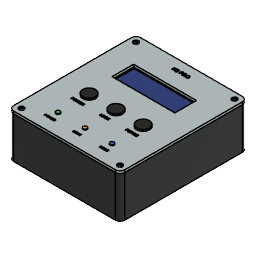
before_v2_edit (Autodesk Fusion 360 design; units mm, degrees)
part number: 2026-09-27-10-19-20-342
part number: 2026-09-27-10-19-20-901
part number: 2026-09-27-10-19-24-013
part number: 2026-09-27-10-19-37-450
part number: 2026-09-27-10-19-39-666
part number: 2026-09-27-10-19-42-130
part number: 2026-09-27-10-19-44-621
part number: 2026-09-27-10-19-47-336
Autodesk Fusion 360 part; units mm, degrees
sketch "Outer shell sketch" plane through (0, 0, 0) normal (0, 0, 1) x (1, 0, 0) in component "01 BASE - PCB at bottom"
  line L0 (6, 0) -> (134, 0)
  line L1 (140, 6) -> (140, 154)
  line L2 (134, 160) -> (6, 160)
  line L3 (0, 154) -> (0, 6)
  arc A0 (134, 0) -> (140, 6) centre (134, 6) ccw
  arc A1 (140, 154) -> (134, 160) centre (134, 154) ccw
  arc A2 (6, 160) -> (0, 154) centre (6, 154) ccw
  arc A3 (0, 6) -> (6, 0) centre (6, 6) ccw
extrude "Outer shell" add sketch "Outer shell sketch" along normal blind 52 makes body 1 in component "01 BASE - PCB at bottom"
ref_plane "WorkPlane1" through (0, 0, 3) normal (0, 0, 1) x (1, 0, 0) in component "01 BASE - PCB at bottom"
sketch "Hollow cavity sketch" plane through (0, 0, 3) normal (0, 0, 1) x (1, 0, 0) in component "01 BASE - PCB at bottom"
  line L0 (6, 3) -> (134, 3)
  line L1 (137, 6) -> (137, 154)
  line L2 (134, 157) -> (6, 157)
  line L3 (3, 154) -> (3, 6)
  arc A0 (134, 3) -> (137, 6) centre (134, 6) ccw
  arc A1 (137, 154) -> (134, 157) centre (134, 154) ccw
  arc A2 (6, 157) -> (3, 154) centre (6, 154) ccw
  arc A3 (3, 6) -> (6, 3) centre (6, 6) ccw
extrude "Hollow cavity" cut sketch "Hollow cavity sketch" along normal blind 50 bodies 1 in component "01 BASE - PCB at bottom"
ref_plane "WorkPlane2" through (0, 0, 3) normal (0, 0, 1) x (1, 0, 0) in component "01 BASE - PCB at bottom"
sketch "Four lid screw pillars" plane through (0, 0, 3) normal (0, 0, 1) x (1, 0, 0) in component "01 BASE - PCB at bottom"
  line L0 (3, 3) -> (13, 3)
  line L1 (13, 3) -> (13, 13)
  line L2 (13, 13) -> (3, 13)
  line L3 (3, 13) -> (3, 3)
  line L4 (127, 3) -> (137, 3)
  line L5 (137, 3) -> (137, 13)
  line L6 (137, 13) -> (127, 13)
  line L7 (127, 13) -> (127, 3)
  line L8 (3, 147) -> (13, 147)
  line L9 (13, 147) -> (13, 157)
  line L10 (13, 157) -> (3, 157)
  line L11 (3, 157) -> (3, 147)
  line L12 (127, 147) -> (137, 147)
  line L13 (137, 147) -> (137, 157)
  line L14 (137, 157) -> (127, 157)
  line L15 (127, 157) -> (127, 147)
extrude "Lid pillars" add sketch "Four lid screw pillars" along normal blind 49 bodies 1 in component "01 BASE - PCB at bottom"
ref_plane "WorkPlane3" through (0, 0, 40) normal (0, 0, 1) x (1, 0, 0) in component "01 BASE - PCB at bottom"
sketch "M3 lid pilot holes sketch" plane through (0, 0, 40) normal (0, 0, 1) x (1, 0, 0) in component "01 BASE - PCB at bottom"
  circle A0 centre (8, 8) radius 1.25
  circle A1 centre (132, 8) radius 1.25
  circle A2 centre (8, 152) radius 1.25
  circle A3 centre (132, 152) radius 1.25
  dimension "d17" = 2.5
  dimension "d18" = 2.5
  dimension "d19" = 2.5
  dimension "d20" = 2.5
  measures "d17" diameter of A0
  measures "d18" diameter of A1
  measures "d19" diameter of A2
  measures "d20" diameter of A3
extrude "M3 lid pilot holes" cut sketch "M3 lid pilot holes sketch" along normal blind 12.1 bodies 1 in component "01 BASE - PCB at bottom"
ref_plane "WorkPlane4" through (0, 0, 3) normal (0, 0, 1) x (1, 0, 0) in component "01 BASE - PCB at bottom"
sketch "PCB support pads" plane through (0, 0, 3) normal (0, 0, 1) x (1, 0, 0) in component "01 BASE - PCB at bottom"
  line L0 (23, 40) -> (29, 40)
  line L1 (29, 40) -> (29, 50)
  line L2 (29, 50) -> (23, 50)
  line L3 (23, 50) -> (23, 40)
  line L4 (23, 110) -> (29, 110)
  line L5 (29, 110) -> (29, 120)
  line L6 (29, 120) -> (23, 120)
  line L7 (23, 120) -> (23, 110)
  line L8 (111, 40) -> (117, 40)
  line L9 (117, 40) -> (117, 50)
  line L10 (117, 50) -> (111, 50)
  line L11 (111, 50) -> (111, 40)
  line L12 (111, 110) -> (117, 110)
  line L13 (117, 110) -> (117, 120)
  line L14 (117, 120) -> (111, 120)
  line L15 (111, 120) -> (111, 110)
extrude "PCB supports z8" add sketch "PCB support pads" along normal blind 5 bodies 1 in component "01 BASE - PCB at bottom"
ref_plane "WorkPlane5" through (0, 0, 3) normal (0, 0, 1) x (1, 0, 0) in component "01 BASE - PCB at bottom"
sketch "PCB lateral guides" plane through (0, 0, 3) normal (0, 0, 1) x (1, 0, 0) in component "01 BASE - PCB at bottom"
  line L0 (22.2, 40) -> (24.6, 40)
  line L1 (24.6, 40) -> (24.6, 50)
  line L2 (24.6, 50) -> (22.2, 50)
  line L3 (22.2, 50) -> (22.2, 40)
  line L4 (22.2, 110) -> (24.6, 110)
  line L5 (24.6, 110) -> (24.6, 120)
  line L6 (24.6, 120) -> (22.2, 120)
  line L7 (22.2, 120) -> (22.2, 110)
  line L8 (115.4, 40) -> (117.8, 40)
  line L9 (117.8, 40) -> (117.8, 50)
  line L10 (117.8, 50) -> (115.4, 50)
  line L11 (115.4, 50) -> (115.4, 40)
  line L12 (115.4, 110) -> (117.8, 110)
  line L13 (117.8, 110) -> (117.8, 120)
  line L14 (117.8, 120) -> (115.4, 120)
  line L15 (115.4, 120) -> (115.4, 110)
  line L16 (55, 27.2) -> (85, 27.2)
  line L17 (85, 27.2) -> (85, 29.6)
  line L18 (85, 29.6) -> (55, 29.6)
  line L19 (55, 29.6) -> (55, 27.2)
  line L20 (55, 130.4) -> (85, 130.4)
  line L21 (85, 130.4) -> (85, 132.8)
  line L22 (85, 132.8) -> (55, 132.8)
  line L23 (55, 132.8) -> (55, 130.4)
extrude "Board edge guides clearance 0.4" add sketch "PCB lateral guides" along normal blind 6.6 bodies 1 in component "01 BASE - PCB at bottom"
ref_plane "WorkPlane6" through (0, 0, 3) normal (0, 0, 1) x (1, 0, 0) in component "01 BASE - PCB at bottom"
sketch "Clamp screw pedestals sketch" plane through (0, 0, 3) normal (0, 0, 1) x (1, 0, 0) in component "01 BASE - PCB at bottom"
  circle A0 centre (20, 45) radius 4
  circle A1 centre (120, 45) radius 4
  circle A2 centre (20, 115) radius 4
  circle A3 centre (120, 115) radius 4
extrude "Clamp screw pedestals" add sketch "Clamp screw pedestals sketch" along normal blind 6.6 bodies 1 in component "01 BASE - PCB at bottom"
ref_plane "WorkPlane7" through (0, 0, 3.1) normal (0, 0, 1) x (1, 0, 0) in component "01 BASE - PCB at bottom"
sketch "M3 clamp pilots sketch" plane through (0, 0, 3.1) normal (0, 0, 1) x (1, 0, 0) in component "01 BASE - PCB at bottom"
  circle A0 centre (20, 45) radius 1.25
  circle A1 centre (120, 45) radius 1.25
  circle A2 centre (20, 115) radius 1.25
  circle A3 centre (120, 115) radius 1.25
  dimension "d37" = 2.5
  dimension "d38" = 2.5
  dimension "d39" = 2.5
  dimension "d40" = 2.5
  measures "d37" diameter of A0
  measures "d38" diameter of A1
  measures "d39" diameter of A2
  measures "d40" diameter of A3
extrude "M3 clamp pilots" cut sketch "M3 clamp pilots sketch" along normal blind 6.6 bodies 1 in component "01 BASE - PCB at bottom"
ref_plane "WorkPlane1" through (0, 0, 52) normal (0, 0, 1) x (1, 0, 0) in component "02 LID - LCD buttons LEDs"
sketch "Lid plate sketch" plane through (0, 0, 52) normal (0, 0, 1) x (1, 0, 0) in component "02 LID - LCD buttons LEDs"
  line L0 (6, 0) -> (134, 0)
  line L1 (140, 6) -> (140, 154)
  line L2 (134, 160) -> (6, 160)
  line L3 (0, 154) -> (0, 6)
  arc A0 (134, 0) -> (140, 6) centre (134, 6) ccw
  arc A1 (140, 154) -> (134, 160) centre (134, 154) ccw
  arc A2 (6, 160) -> (0, 154) centre (6, 154) ccw
  arc A3 (0, 6) -> (6, 0) centre (6, 6) ccw
extrude "Lid plate" add sketch "Lid plate sketch" along normal blind 3 separate body makes body 2 in component "02 LID - LCD buttons LEDs"
ref_plane "WorkPlane2" through (0, 0, 48) normal (0, 0, 1) x (1, 0, 0) in component "02 LID - LCD buttons LEDs"
sketch "Locating lip segments - 0.3 clearance" plane through (0, 0, 48) normal (0, 0, 1) x (1, 0, 0) in component "02 LID - LCD buttons LEDs"
  line L0 (3.3, 16) -> (5.3, 16)
  line L1 (5.3, 16) -> (5.3, 144)
  line L2 (5.3, 144) -> (3.3, 144)
  line L3 (3.3, 144) -> (3.3, 16)
  line L4 (134.7, 16) -> (136.7, 16)
  line L5 (136.7, 16) -> (136.7, 144)
  line L6 (136.7, 144) -> (134.7, 144)
  line L7 (134.7, 144) -> (134.7, 16)
  line L8 (16, 3.3) -> (124, 3.3)
  line L9 (124, 3.3) -> (124, 5.3)
  line L10 (124, 5.3) -> (16, 5.3)
  line L11 (16, 5.3) -> (16, 3.3)
  line L12 (16, 154.7) -> (124, 154.7)
  line L13 (124, 154.7) -> (124, 156.7)
  line L14 (124, 156.7) -> (16, 156.7)
  line L15 (16, 156.7) -> (16, 154.7)
extrude "Locating lips" add sketch "Locating lip segments - 0.3 clearance" along normal blind 4 bodies 2 in component "02 LID - LCD buttons LEDs"
ref_plane "WorkPlane3" through (0, 0, 51.9) normal (0, 0, 1) x (1, 0, 0) in component "02 LID - LCD buttons LEDs"
sketch "M3 lid through holes sketch" plane through (0, 0, 51.9) normal (0, 0, 1) x (1, 0, 0) in component "02 LID - LCD buttons LEDs"
  circle A0 centre (8, 8) radius 1.7
  circle A1 centre (132, 8) radius 1.7
  circle A2 centre (8, 152) radius 1.7
  circle A3 centre (132, 152) radius 1.7
  dimension "d53" = 3.4
  dimension "d54" = 3.4
  dimension "d55" = 3.4
  dimension "d56" = 3.4
  measures "d53" diameter of A0
  measures "d54" diameter of A1
  measures "d55" diameter of A2
  measures "d56" diameter of A3
extrude "M3 lid through holes" cut sketch "M3 lid through holes sketch" along normal blind 3.2 bodies 2 in component "02 LID - LCD buttons LEDs"
ref_plane "WorkPlane4" through (0, 0, 53.8) normal (0, 0, 1) x (1, 0, 0) in component "02 LID - LCD buttons LEDs"
sketch "Screw head pockets sketch" plane through (0, 0, 53.8) normal (0, 0, 1) x (1, 0, 0) in component "02 LID - LCD buttons LEDs"
  circle A0 centre (8, 8) radius 3.2
  circle A1 centre (132, 8) radius 3.2
  circle A2 centre (8, 152) radius 3.2
  circle A3 centre (132, 152) radius 3.2
extrude "Screw head pockets" cut sketch "Screw head pockets sketch" along normal blind 1.3 bodies 2 in component "02 LID - LCD buttons LEDs"
ref_plane "WorkPlane5" through (0, 0, 51.9) normal (0, 0, 1) x (1, 0, 0) in component "02 LID - LCD buttons LEDs"
sketch "LCD viewing aperture sketch" plane through (0, 0, 51.9) normal (0, 0, 1) x (1, 0, 0) in component "02 LID - LCD buttons LEDs"
  line L0 (30.5, 99.5) -> (109.5, 99.5)
  line L1 (109.5, 99.5) -> (109.5, 126.5)
  line L2 (109.5, 126.5) -> (30.5, 126.5)
  line L3 (30.5, 126.5) -> (30.5, 99.5)
extrude "LCD viewing aperture" cut sketch "LCD viewing aperture sketch" along normal blind 3.2 bodies 2 in component "02 LID - LCD buttons LEDs"
ref_plane "WorkPlane6" through (0, 0, 42) normal (0, 0, 1) x (1, 0, 0) in component "02 LID - LCD buttons LEDs"
sketch "LCD underside spacers sketch" plane through (0, 0, 42) normal (0, 0, 1) x (1, 0, 0) in component "02 LID - LCD buttons LEDs"
  circle A0 centre (23.5, 85.5) radius 3.5
  circle A1 centre (116.5, 85.5) radius 3.5
  circle A2 centre (23.5, 140.5) radius 3.5
  circle A3 centre (116.5, 140.5) radius 3.5
extrude "LCD underside spacers" add sketch "LCD underside spacers sketch" along normal blind 10 bodies 2 in component "02 LID - LCD buttons LEDs"
ref_plane "WorkPlane7" through (0, 0, 41.9) normal (0, 0, 1) x (1, 0, 0) in component "02 LID - LCD buttons LEDs"
sketch "LCD M3 pilot holes sketch" plane through (0, 0, 41.9) normal (0, 0, 1) x (1, 0, 0) in component "02 LID - LCD buttons LEDs"
  circle A0 centre (23.5, 85.5) radius 1.25
  circle A1 centre (116.5, 85.5) radius 1.25
  circle A2 centre (23.5, 140.5) radius 1.25
  circle A3 centre (116.5, 140.5) radius 1.25
  dimension "d73" = 2.5
  dimension "d74" = 2.5
  dimension "d75" = 2.5
  dimension "d76" = 2.5
  measures "d73" diameter of A0
  measures "d74" diameter of A1
  measures "d75" diameter of A2
  measures "d76" diameter of A3
extrude "LCD M3 pilot holes" cut sketch "LCD M3 pilot holes sketch" along normal blind 8.1 bodies 2 in component "02 LID - LCD buttons LEDs"
ref_plane "WorkPlane8" through (0, 0, 51.9) normal (0, 0, 1) x (1, 0, 0) in component "02 LID - LCD buttons LEDs"
sketch "Three panel buttons sketch" plane through (0, 0, 51.9) normal (0, 0, 1) x (1, 0, 0) in component "02 LID - LCD buttons LEDs"
  circle A0 centre (36, 65) radius 6.1
  circle A1 centre (70, 65) radius 6.1
  circle A2 centre (104, 65) radius 6.1
  dimension "d81" = 12.2
  dimension "d82" = 12.2
  dimension "d83" = 12.2
  measures "d81" diameter of A0
  measures "d82" diameter of A1
  measures "d83" diameter of A2
extrude "Three panel buttons" cut sketch "Three panel buttons sketch" along normal blind 3.2 bodies 2 in component "02 LID - LCD buttons LEDs"
ref_plane "WorkPlane9" through (0, 0, 51.9) normal (0, 0, 1) x (1, 0, 0) in component "02 LID - LCD buttons LEDs"
sketch "Three indicator LEDs sketch" plane through (0, 0, 51.9) normal (0, 0, 1) x (1, 0, 0) in component "02 LID - LCD buttons LEDs"
  circle A0 centre (36, 26) radius 2.6
  circle A1 centre (70, 26) radius 2.6
  circle A2 centre (104, 26) radius 2.6
  dimension "d88" = 5.2
  dimension "d89" = 5.2
  dimension "d90" = 5.2
  measures "d88" diameter of A0
  measures "d89" diameter of A1
  measures "d90" diameter of A2
extrude "Three indicator LEDs" cut sketch "Three indicator LEDs sketch" along normal blind 3.2 bodies 2 in component "02 LID - LCD buttons LEDs"
ref_plane "WorkPlane10" through (0, 0, 55) normal (0, 0, 1) x (1, 0, 0) in component "02 LID - LCD buttons LEDs"
sketch "Engraving H2 PRO" plane through (0, 0, 55) normal (0, 0, 1) x (1, 0, 0) in component "02 LID - LCD buttons LEDs"
  line L0 (37.5, 144.5) -> (102.5, 144.5) construction
  line L1 (102.5, 144.5) -> (102.5, 149.5) construction
  line L2 (102.5, 149.5) -> (37.5, 149.5) construction
  line L3 (37.5, 149.5) -> (37.5, 144.5) construction
  dimension "d95" = 4
  dimension "d96" = 0
  text T0 "H2 PRO" font "Arial" height 4 align centre middle in box 65 x 5 at (37.5, 144.5) x (1, 0) y (0, 1) spacing 1 kerned
extrude "Engrave H2 PRO" cut sketch "Engraving H2 PRO" against normal blind 0.4 text T0 bodies 2 in component "02 LID - LCD buttons LEDs"
ref_plane "WorkPlane11" through (0, 0, 55) normal (0, 0, 1) x (1, 0, 0) in component "02 LID - LCD buttons LEDs"
sketch "Engraving POWER" plane through (0, 0, 55) normal (0, 0, 1) x (1, 0, 0) in component "02 LID - LCD buttons LEDs"
  line L0 (21, 48.5) -> (51, 48.5) construction
  line L1 (51, 48.5) -> (51, 53.5) construction
  line L2 (51, 53.5) -> (21, 53.5) construction
  line L3 (21, 53.5) -> (21, 48.5) construction
  dimension "d101" = 3
  text T0 "POWER" font "Arial" height 3 align centre middle in box 30 x 5 at (21, 48.5) x (1, 0) y (0, 1) spacing 1 kerned
extrude "Engrave POWER" cut sketch "Engraving POWER" against normal blind 0.4 text T0 bodies 2 in component "02 LID - LCD buttons LEDs"
ref_plane "WorkPlane12" through (0, 0, 55) normal (0, 0, 1) x (1, 0, 0) in component "02 LID - LCD buttons LEDs"
sketch "Engraving LOCK" plane through (0, 0, 55) normal (0, 0, 1) x (1, 0, 0) in component "02 LID - LCD buttons LEDs"
  line L0 (55, 48.5) -> (85, 48.5) construction
  line L1 (85, 48.5) -> (85, 53.5) construction
  line L2 (85, 53.5) -> (55, 53.5) construction
  line L3 (55, 53.5) -> (55, 48.5) construction
  dimension "d107" = 3
  text T0 "LOCK" font "Arial" height 3 align centre middle in box 30 x 5 at (55, 48.5) x (1, 0) y (0, 1) spacing 1 kerned
extrude "Engrave LOCK" cut sketch "Engraving LOCK" against normal blind 0.4 text T0 bodies 2 in component "02 LID - LCD buttons LEDs"
ref_plane "WorkPlane13" through (0, 0, 55) normal (0, 0, 1) x (1, 0, 0) in component "02 LID - LCD buttons LEDs"
sketch "Engraving PURGE" plane through (0, 0, 55) normal (0, 0, 1) x (1, 0, 0) in component "02 LID - LCD buttons LEDs"
  line L0 (89, 48.5) -> (119, 48.5) construction
  line L1 (119, 48.5) -> (119, 53.5) construction
  line L2 (119, 53.5) -> (89, 53.5) construction
  line L3 (89, 53.5) -> (89, 48.5) construction
  dimension "d113" = 3
  text T0 "PURGE" font "Arial" height 3 align centre middle in box 30 x 5 at (89, 48.5) x (1, 0) y (0, 1) spacing 1 kerned
extrude "Engrave PURGE" cut sketch "Engraving PURGE" against normal blind 0.4 text T0 bodies 2 in component "02 LID - LCD buttons LEDs"
ref_plane "WorkPlane14" through (0, 0, 55) normal (0, 0, 1) x (1, 0, 0) in component "02 LID - LCD buttons LEDs"
sketch "Engraving POWER (1)" plane through (0, 0, 55) normal (0, 0, 1) x (1, 0, 0) in component "02 LID - LCD buttons LEDs"
  line L0 (21, 13.5) -> (51, 13.5) construction
  line L1 (51, 13.5) -> (51, 18.5) construction
  line L2 (51, 18.5) -> (21, 18.5) construction
  line L3 (21, 18.5) -> (21, 13.5) construction
  dimension "d119" = 2.5
  text T0 "POWER" font "Arial" height 2.5 align centre middle in box 30 x 5 at (21, 13.5) x (1, 0) y (0, 1) spacing 1 kerned
extrude "Engrave POWER (1)" cut sketch "Engraving POWER (1)" against normal blind 0.4 text T0 bodies 2 in component "02 LID - LCD buttons LEDs"
ref_plane "WorkPlane15" through (0, 0, 55) normal (0, 0, 1) x (1, 0, 0) in component "02 LID - LCD buttons LEDs"
sketch "Engraving LOCK (1)" plane through (0, 0, 55) normal (0, 0, 1) x (1, 0, 0) in component "02 LID - LCD buttons LEDs"
  line L0 (55, 13.5) -> (85, 13.5) construction
  line L1 (85, 13.5) -> (85, 18.5) construction
  line L2 (85, 18.5) -> (55, 18.5) construction
  line L3 (55, 18.5) -> (55, 13.5) construction
  dimension "d125" = 2.5
  text T0 "LOCK" font "Arial" height 2.5 align centre middle in box 30 x 5 at (55, 13.5) x (1, 0) y (0, 1) spacing 1 kerned
extrude "Engrave LOCK (1)" cut sketch "Engraving LOCK (1)" against normal blind 0.4 text T0 bodies 2 in component "02 LID - LCD buttons LEDs"
ref_plane "WorkPlane16" through (0, 0, 55) normal (0, 0, 1) x (1, 0, 0) in component "02 LID - LCD buttons LEDs"
sketch "Engraving MODE" plane through (0, 0, 55) normal (0, 0, 1) x (1, 0, 0) in component "02 LID - LCD buttons LEDs"
  line L0 (89, 13.5) -> (119, 13.5) construction
  line L1 (119, 13.5) -> (119, 18.5) construction
  line L2 (119, 18.5) -> (89, 18.5) construction
  line L3 (89, 18.5) -> (89, 13.5) construction
  dimension "d131" = 2.5
  text T0 "MODE" font "Arial" height 2.5 align centre middle in box 30 x 5 at (89, 13.5) x (1, 0) y (0, 1) spacing 1 kerned
extrude "Engrave MODE" cut sketch "Engraving MODE" against normal blind 0.4 text T0 bodies 2 in component "02 LID - LCD buttons LEDs"
ref_plane "WorkPlane1" through (0, 0, 9.6) normal (0, 0, 1) x (1, 0, 0) in component "03 PCB clamp 1"
sketch "Removable edge clamp sketch" plane through (0, 0, 9.6) normal (0, 0, 1) x (1, 0, 0) in component "03 PCB clamp 1"
  line L0 (17, 40) -> (27.5, 40)
  line L1 (28.5, 41) -> (28.5, 49)
  line L2 (27.5, 50) -> (17, 50)
  line L3 (16, 49) -> (16, 41)
  arc A0 (27.5, 40) -> (28.5, 41) centre (27.5, 41) ccw
  arc A1 (28.5, 49) -> (27.5, 50) centre (27.5, 49) ccw
  arc A2 (17, 50) -> (16, 49) centre (17, 49) ccw
  arc A3 (16, 41) -> (17, 40) centre (17, 41) ccw
extrude "Removable edge clamp" add sketch "Removable edge clamp sketch" along normal blind 2.5 separate body makes body 3 in component "03 PCB clamp 1"
ref_plane "WorkPlane2" through (0, 0, 9.5) normal (0, 0, 1) x (1, 0, 0) in component "03 PCB clamp 1"
sketch "Clamp screw clearance sketch" plane through (0, 0, 9.5) normal (0, 0, 1) x (1, 0, 0) in component "03 PCB clamp 1"
  circle A0 centre (20, 45) radius 1.7
  dimension "d141" = 3.4
  measures "d141" diameter of A0
extrude "Clamp screw clearance" cut sketch "Clamp screw clearance sketch" along normal blind 2.7 bodies 3 in component "03 PCB clamp 1"
ref_plane "WorkPlane1" through (0, 0, 9.6) normal (0, 0, 1) x (1, 0, 0) in component "03 PCB clamp 2"
sketch "Removable edge clamp sketch (2)" plane through (0, 0, 9.6) normal (0, 0, 1) x (1, 0, 0) in component "03 PCB clamp 2"
  line L0 (112.5, 40) -> (123, 40)
  line L1 (124, 41) -> (124, 49)
  line L2 (123, 50) -> (112.5, 50)
  line L3 (111.5, 49) -> (111.5, 41)
  arc A0 (123, 40) -> (124, 41) centre (123, 41) ccw
  arc A1 (124, 49) -> (123, 50) centre (123, 49) ccw
  arc A2 (112.5, 50) -> (111.5, 49) centre (112.5, 49) ccw
  arc A3 (111.5, 41) -> (112.5, 40) centre (112.5, 41) ccw
extrude "Removable edge clamp'" add sketch "Removable edge clamp sketch (2)" along normal blind 2.5 separate body makes body 4 in component "03 PCB clamp 2"
ref_plane "WorkPlane2" through (0, 0, 9.5) normal (0, 0, 1) x (1, 0, 0) in component "03 PCB clamp 2"
sketch "Clamp screw clearance sketch (2)" plane through (0, 0, 9.5) normal (0, 0, 1) x (1, 0, 0) in component "03 PCB clamp 2"
  circle A0 centre (120, 45) radius 1.7
  dimension "d150" = 3.4
  measures "d150" diameter of A0
extrude "Clamp screw clearance'" cut sketch "Clamp screw clearance sketch (2)" along normal blind 2.7 bodies 4 in component "03 PCB clamp 2"
ref_plane "WorkPlane1" through (0, 0, 9.6) normal (0, 0, 1) x (1, 0, 0) in component "03 PCB clamp 3"
sketch "Removable edge clamp sketch (3)" plane through (0, 0, 9.6) normal (0, 0, 1) x (1, 0, 0) in component "03 PCB clamp 3"
  line L0 (17, 110) -> (27.5, 110)
  line L1 (28.5, 111) -> (28.5, 119)
  line L2 (27.5, 120) -> (17, 120)
  line L3 (16, 119) -> (16, 111)
  arc A0 (27.5, 110) -> (28.5, 111) centre (27.5, 111) ccw
  arc A1 (28.5, 119) -> (27.5, 120) centre (27.5, 119) ccw
  arc A2 (17, 120) -> (16, 119) centre (17, 119) ccw
  arc A3 (16, 111) -> (17, 110) centre (17, 111) ccw
extrude "Removable edge clamp''" add sketch "Removable edge clamp sketch (3)" along normal blind 2.5 separate body makes body 5 in component "03 PCB clamp 3"
ref_plane "WorkPlane2" through (0, 0, 9.5) normal (0, 0, 1) x (1, 0, 0) in component "03 PCB clamp 3"
sketch "Clamp screw clearance sketch (3)" plane through (0, 0, 9.5) normal (0, 0, 1) x (1, 0, 0) in component "03 PCB clamp 3"
  circle A0 centre (20, 115) radius 1.7
  dimension "d159" = 3.4
  measures "d159" diameter of A0
extrude "Clamp screw clearance''" cut sketch "Clamp screw clearance sketch (3)" along normal blind 2.7 bodies 5 in component "03 PCB clamp 3"
ref_plane "WorkPlane1" through (0, 0, 9.6) normal (0, 0, 1) x (1, 0, 0) in component "03 PCB clamp 4"
sketch "Removable edge clamp sketch (4)" plane through (0, 0, 9.6) normal (0, 0, 1) x (1, 0, 0) in component "03 PCB clamp 4"
  line L0 (112.5, 110) -> (123, 110)
  line L1 (124, 111) -> (124, 119)
  line L2 (123, 120) -> (112.5, 120)
  line L3 (111.5, 119) -> (111.5, 111)
  arc A0 (123, 110) -> (124, 111) centre (123, 111) ccw
  arc A1 (124, 119) -> (123, 120) centre (123, 119) ccw
  arc A2 (112.5, 120) -> (111.5, 119) centre (112.5, 119) ccw
  arc A3 (111.5, 111) -> (112.5, 110) centre (112.5, 111) ccw
extrude "Removable edge clamp'''" add sketch "Removable edge clamp sketch (4)" along normal blind 2.5 separate body makes body 6 in component "03 PCB clamp 4"
ref_plane "WorkPlane2" through (0, 0, 9.5) normal (0, 0, 1) x (1, 0, 0) in component "03 PCB clamp 4"
sketch "Clamp screw clearance sketch (4)" plane through (0, 0, 9.5) normal (0, 0, 1) x (1, 0, 0) in component "03 PCB clamp 4"
  circle A0 centre (120, 115) radius 1.7
  dimension "d168" = 3.4
  measures "d168" diameter of A0
extrude "Clamp screw clearance'''" cut sketch "Clamp screw clearance sketch (4)" along normal blind 2.7 bodies 6 in component "03 PCB clamp 4"
ref_plane "WorkPlane1" through (0, 0, 8) normal (0, 0, 1) x (1, 0, 0) in component "90 REFERENCES - DO NOT PRINT"
sketch "Main PCB 90x100 reference sketch" plane through (0, 0, 8) normal (0, 0, 1) x (1, 0, 0) in component "90 REFERENCES - DO NOT PRINT"
  line L0 (25, 30) -> (115, 30)
  line L1 (115, 30) -> (115, 130)
  line L2 (115, 130) -> (25, 130)
  line L3 (25, 130) -> (25, 30)
extrude "Main PCB 90x100 reference" add sketch "Main PCB 90x100 reference sketch" along normal blind 1.6 separate body makes body 7 in component "90 REFERENCES - DO NOT PRINT"
ref_plane "WorkPlane2" through (0, 0, 9.6) normal (0, 0, 1) x (1, 0, 0) in component "90 REFERENCES - DO NOT PRINT"
sketch "Main board component keepout to z23 sketch" plane through (0, 0, 9.6) normal (0, 0, 1) x (1, 0, 0) in component "90 REFERENCES - DO NOT PRINT"
  line L0 (28.5, 33.5) -> (111.5, 33.5)
  line L1 (111.5, 33.5) -> (111.5, 126.5)
  line L2 (111.5, 126.5) -> (28.5, 126.5)
  line L3 (28.5, 126.5) -> (28.5, 33.5)
extrude "Main board component keepout to z23" add sketch "Main board component keepout to z23 sketch" along normal blind 13.4 separate body makes body 8 in component "90 REFERENCES - DO NOT PRINT"
ref_plane "WorkPlane3" through (0, 0, 40.4) normal (0, 0, 1) x (1, 0, 0) in component "90 REFERENCES - DO NOT PRINT"
sketch "LCD2004 PCB assumed 98x60 sketch" plane through (0, 0, 40.4) normal (0, 0, 1) x (1, 0, 0) in component "90 REFERENCES - DO NOT PRINT"
  line L0 (21, 83) -> (119, 83)
  line L1 (119, 83) -> (119, 143)
  line L2 (119, 143) -> (21, 143)
  line L3 (21, 143) -> (21, 83)
extrude "LCD2004 PCB assumed 98x60" add sketch "LCD2004 PCB assumed 98x60 sketch" along normal blind 1.6 separate body makes body 9 in component "90 REFERENCES - DO NOT PRINT"
ref_plane "WorkPlane4" through (0, 0, 40.3) normal (0, 0, 1) x (1, 0, 0) in component "90 REFERENCES - DO NOT PRINT"
sketch "LCD PCB mounting reference sketch" plane through (0, 0, 40.3) normal (0, 0, 1) x (1, 0, 0) in component "90 REFERENCES - DO NOT PRINT"
  circle A0 centre (23.5, 85.5) radius 1.6
  circle A1 centre (116.5, 85.5) radius 1.6
  circle A2 centre (23.5, 140.5) radius 1.6
  circle A3 centre (116.5, 140.5) radius 1.6
extrude "LCD PCB mounting reference" cut sketch "LCD PCB mounting reference sketch" along normal blind 1.8 bodies 9 in component "90 REFERENCES - DO NOT PRINT"
ref_plane "WorkPlane5" through (0, 0, 42) normal (0, 0, 1) x (1, 0, 0) in component "90 REFERENCES - DO NOT PRINT"
sketch "LCD metal frame reference sketch" plane through (0, 0, 42) normal (0, 0, 1) x (1, 0, 0) in component "90 REFERENCES - DO NOT PRINT"
  line L0 (21.5, 93.5) -> (118.5, 93.5)
  line L1 (118.5, 93.5) -> (118.5, 132.5)
  line L2 (118.5, 132.5) -> (21.5, 132.5)
  line L3 (21.5, 132.5) -> (21.5, 93.5)
extrude "LCD metal frame reference" add sketch "LCD metal frame reference sketch" along normal blind 9.5 separate body makes body 10 in component "90 REFERENCES - DO NOT PRINT"
ref_plane "WorkPlane6" through (0, 0, 51.5) normal (0, 0, 1) x (1, 0, 0) in component "90 REFERENCES - DO NOT PRINT"
sketch "LCD visible glass reference sketch" plane through (0, 0, 51.5) normal (0, 0, 1) x (1, 0, 0) in component "90 REFERENCES - DO NOT PRINT"
  line L0 (32, 100.4) -> (108, 100.4)
  line L1 (108, 100.4) -> (108, 125.6)
  line L2 (108, 125.6) -> (32, 125.6)
  line L3 (32, 125.6) -> (32, 100.4)
extrude "LCD visible glass reference" add sketch "LCD visible glass reference sketch" along normal blind 0.3 separate body makes body 11 in component "90 REFERENCES - DO NOT PRINT"
ref_plane "WorkPlane7" through (0, 0, 30) normal (0, 0, 1) x (1, 0, 0) in component "90 REFERENCES - DO NOT PRINT"
sketch "I2C backpack reserved volume sketch" plane through (0, 0, 30) normal (0, 0, 1) x (1, 0, 0) in component "90 REFERENCES - DO NOT PRINT"
  line L0 (32, 85) -> (74, 85)
  line L1 (74, 85) -> (74, 103)
  line L2 (74, 103) -> (32, 103)
  line L3 (32, 103) -> (32, 85)
extrude "I2C backpack reserved volume" add sketch "I2C backpack reserved volume sketch" along normal blind 10.4 separate body makes body 12 in component "90 REFERENCES - DO NOT PRINT"
ref_plane "WorkPlane8" through (0, 0, 37) normal (0, 0, 1) x (1, 0, 0) in component "90 REFERENCES - DO NOT PRINT"
sketch "Button body reference" plane through (0, 0, 37) normal (0, 0, 1) x (1, 0, 0) in component "90 REFERENCES - DO NOT PRINT"
  circle A0 centre (36, 65) radius 6
extrude "Panel button barrel reference" add sketch "Button body reference" along normal blind 18 separate body makes body 13 in component "90 REFERENCES - DO NOT PRINT"
ref_plane "WorkPlane9" through (0, 0, 55) normal (0, 0, 1) x (1, 0, 0) in component "90 REFERENCES - DO NOT PRINT"
sketch "Button cap reference" plane through (0, 0, 55) normal (0, 0, 1) x (1, 0, 0) in component "90 REFERENCES - DO NOT PRINT"
  circle A0 centre (36, 65) radius 8
extrude "Button cap reference (1)" add sketch "Button cap reference" along normal blind 2 separate body makes body 14 in component "90 REFERENCES - DO NOT PRINT"
ref_plane "WorkPlane10" through (0, 0, 37) normal (0, 0, 1) x (1, 0, 0) in component "90 REFERENCES - DO NOT PRINT"
sketch "Button body reference (1)" plane through (0, 0, 37) normal (0, 0, 1) x (1, 0, 0) in component "90 REFERENCES - DO NOT PRINT"
  circle A0 centre (70, 65) radius 6
extrude "Panel button barrel reference (1)" add sketch "Button body reference (1)" along normal blind 18 separate body makes body 15 in component "90 REFERENCES - DO NOT PRINT"
ref_plane "WorkPlane11" through (0, 0, 55) normal (0, 0, 1) x (1, 0, 0) in component "90 REFERENCES - DO NOT PRINT"
sketch "Button cap reference (1)" plane through (0, 0, 55) normal (0, 0, 1) x (1, 0, 0) in component "90 REFERENCES - DO NOT PRINT"
  circle A0 centre (70, 65) radius 8
extrude "Button cap reference (2)" add sketch "Button cap reference (1)" along normal blind 2 separate body makes body 16 in component "90 REFERENCES - DO NOT PRINT"
ref_plane "WorkPlane12" through (0, 0, 37) normal (0, 0, 1) x (1, 0, 0) in component "90 REFERENCES - DO NOT PRINT"
sketch "Button body reference (2)" plane through (0, 0, 37) normal (0, 0, 1) x (1, 0, 0) in component "90 REFERENCES - DO NOT PRINT"
  circle A0 centre (104, 65) radius 6
extrude "Panel button barrel reference (2)" add sketch "Button body reference (2)" along normal blind 18 separate body makes body 17 in component "90 REFERENCES - DO NOT PRINT"
ref_plane "WorkPlane13" through (0, 0, 55) normal (0, 0, 1) x (1, 0, 0) in component "90 REFERENCES - DO NOT PRINT"
sketch "Button cap reference (2)" plane through (0, 0, 55) normal (0, 0, 1) x (1, 0, 0) in component "90 REFERENCES - DO NOT PRINT"
  circle A0 centre (104, 65) radius 8
extrude "Button cap reference (3)" add sketch "Button cap reference (2)" along normal blind 2 separate body makes body 18 in component "90 REFERENCES - DO NOT PRINT"
ref_plane "WorkPlane14" through (0, 0, 51) normal (0, 0, 1) x (1, 0, 0) in component "90 REFERENCES - DO NOT PRINT"
sketch "LED reference" plane through (0, 0, 51) normal (0, 0, 1) x (1, 0, 0) in component "90 REFERENCES - DO NOT PRINT"
  circle A0 centre (36, 26) radius 2.5
extrude "LED 5mm reference" add sketch "LED reference" along normal blind 5 separate body makes body 19 in component "90 REFERENCES - DO NOT PRINT"
ref_plane "WorkPlane15" through (0, 0, 51) normal (0, 0, 1) x (1, 0, 0) in component "90 REFERENCES - DO NOT PRINT"
sketch "LED reference (1)" plane through (0, 0, 51) normal (0, 0, 1) x (1, 0, 0) in component "90 REFERENCES - DO NOT PRINT"
  circle A0 centre (70, 26) radius 2.5
extrude "LED 5mm reference (1)" add sketch "LED reference (1)" along normal blind 5 separate body makes body 20 in component "90 REFERENCES - DO NOT PRINT"
ref_plane "WorkPlane16" through (0, 0, 51) normal (0, 0, 1) x (1, 0, 0) in component "90 REFERENCES - DO NOT PRINT"
sketch "LED reference (2)" plane through (0, 0, 51) normal (0, 0, 1) x (1, 0, 0) in component "90 REFERENCES - DO NOT PRINT"
  circle A0 centre (104, 26) radius 2.5
extrude "LED 5mm reference (2)" add sketch "LED reference (2)" along normal blind 5 separate body makes body 21 in component "90 REFERENCES - DO NOT PRINT"
component "01 BASE - PCB at bottom" placed x (1, 0, 0) y (0, 1, 0) z (0, 0, 1) at (0, 0, 0)
component "02 LID - LCD buttons LEDs" placed x (1, 0, 0) y (0, 1, 0) z (0, 0, 1) at (0, 0, 0)
component "03 PCB clamp 1" placed x (1, 0, 0) y (0, 1, 0) z (0, 0, 1) at (0, 0, 0)
component "03 PCB clamp 2" placed x (1, 0, 0) y (0, 1, 0) z (0, 0, 1) at (0, 0, 0)
component "03 PCB clamp 3" placed x (1, 0, 0) y (0, 1, 0) z (0, 0, 1) at (0, 0, 0)
component "03 PCB clamp 4" placed x (1, 0, 0) y (0, 1, 0) z (0, 0, 1) at (0, 0, 0)
component "90 REFERENCES - DO NOT PRINT" placed x (1, 0, 0) y (0, 1, 0) z (0, 0, 1) at (0, 0, 0)
equation "button_d = 12.2 mm" comment "ASSUMED: measure actual panel button"
equation "led_d = 5.2 mm" comment "ASSUMED: 5 mm LED clearance"
equation "screw_clearance = 3.4 mm" comment "M3 clearance"
equation "pilot_d = 2.5 mm" comment "Plastic tapping pilot; verify printed fit"
equation "d17 = pilot_d"
equation "d18 = pilot_d"
equation "d19 = pilot_d"
equation "d20 = pilot_d"
equation "d37 = pilot_d"
equation "d38 = pilot_d"
equation "d39 = pilot_d"
equation "d40 = pilot_d"
equation "d53 = screw_clearance"
equation "d54 = screw_clearance"
equation "d55 = screw_clearance"
equation "d56 = screw_clearance"
equation "d73 = pilot_d"
equation "d74 = pilot_d"
equation "d75 = pilot_d"
equation "d76 = pilot_d"
equation "d81 = button_d"
equation "d82 = button_d"
equation "d83 = button_d"
equation "d88 = led_d"
equation "d89 = led_d"
equation "d90 = led_d"
equation "d96 = 'H2 PRO'"
equation "d102 = 'POWER'"
equation "d108 = 'LOCK'"
equation "d114 = 'PURGE'"
equation "d120 = 'POWER'"
equation "d126 = 'LOCK'"
equation "d132 = 'MODE'"
equation "d141 = screw_clearance"
equation "d150 = screw_clearance"
equation "d159 = screw_clearance"
equation "d168 = screw_clearance"
named bodies: "BASE_PRINT", "LID_PRINT", "CLAMP_PRINT_1", "CLAMP_PRINT_2", "CLAMP_PRINT_3", "CLAMP_PRINT_4", "Main PCB - assumed substrate 1.6", "Component envelope - total height 15 mm", "LCD2004 PCB 98x60", "LCD metal frame", "LCD visible glass", "I2C backpack", "POWER barrel", "POWER cap", "LOCK barrel", "LOCK cap", "PURGE barrel", "PURGE cap", "LED POWER", "LED LOCK", "LED MODE"
